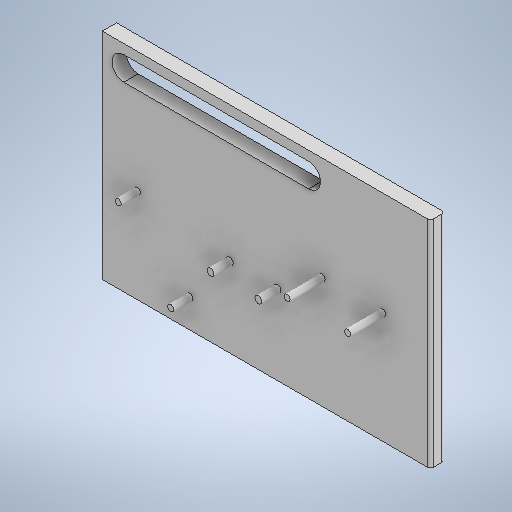
# Autodesk Inventor part: polka
Saved by Autodesk Inventor 2025.2 (Build 292293000, 293)
## iProperties
Created: 2026-10-25
Part Number: polka
Material: Generic
Document SubType Name: Modeling
Designer: Kacper
Density: 1 g/cm^3
Appearance: Default
Author: Kacper
Autodesk Inventor part; units mm, degrees
ref_plane "YZ Plane" through (0, 0, 0) normal (1, 0, 0) x (0, 1, 0)
ref_plane "XZ Plane" through (0, 0, 0) normal (0, 1, 0) x (-1, 0, 0)
ref_plane "XY Plane" through (0, 0, 0) normal (0, 0, 1) x (1, 0, 0)
sketch "Sketch1" plane through (0, 0, 0) normal (0, 0, 1) x (1, 0, 0)
  line L0 (-51.5, 33.75) -> (51.5, 33.75)
  line L1 (51.5, 33.75) -> (51.5, -33.75)
  line L2 (51.5, -33.75) -> (-51.5, -33.75)
  line L3 (-51.5, -33.75) -> (-51.5, 33.75)
  line L4 (-51.5, 33.75) -> (51.5, -33.75) construction
  line L5 (51.5, 33.75) -> (-51.5, -33.75) construction
  point P0 (0, 0)
  dimension "d1" = 67.5
  dimension "d2" = 103
  constraints: 12 end point, 2 midpoint, 2 parallel, 1 horizontal, 1 perpendicular
  measures "d1" distance of L0.end L1.end
  measures "d2" distance of L0.start L0.end
extrude "Extrusion1" add sketch "Sketch1" along normal blind 4.5
sketch "Sketch2" plane through (0, 0, 4.5) normal (0, 0, 1) x (1, 0, 0)
  line L0 (-51.5, -33.75) -> (51.5, -33.75) projected
  line L1 (51.5, -33.75) -> (51.5, 33.75) projected
  line L2 (51.5, 33.75) -> (-51.5, 33.75) projected
  line L3 (-51.5, 33.75) -> (-51.5, -33.75) projected
  line L4 (-44.75, 27) -> (13.25, 27) construction
  line L5 (-44.75, 23.25) -> (13.25, 23.25)
  line L6 (13.25, 30.75) -> (-44.75, 30.75)
  arc A0 (-44.75, 30.75) -> (-44.75, 23.25) centre (-44.75, 27) ccw
  arc A1 (13.25, 23.25) -> (13.25, 30.75) centre (13.25, 27) ccw
  point P0 (0, 0)
  point P1 (-15.75, 27)
  point P2 (17, 27)
  point P3 (-48.5, 27)
  point P4 (-15.75, 30.75)
  point P5 (-15.75, 23.25)
  dimension "d6" = 3
  dimension "d7" = 7.5
  dimension "d8" = 3
  dimension "d9" = 58
  constraints: 8 end point, 6 point on circle, 4 tangent, 3 midpoint, 2 centre point, 2 parallel, 1 horizontal
  measures "d6" distance from line of L3 point (-48.5, 27)
  measures "d7" distance of point (-15.75, 30.75) point (-15.75, 23.25)
  measures "d8" distance between parallel lines of L2 L6
  measures "d9" distance of L6.start L6.end
extrude "Extrusion2" cut sketch "Sketch2" against normal up to surface (4.5 mm away) contours A0 L6 A1 L5
sketch "Sketch3" plane through (0, 0, 4.5) normal (0, 0, 1) x (1, 0, 0)
  arc A0 (13.25, 23.25) -> (13.25, 30.75) centre (13.25, 27) ccw projected
  line L0 (13.25, 23.25) -> (-44.75, 23.25) projected
  arc A1 (-44.75, 30.75) -> (-44.75, 23.25) centre (-44.75, 27) ccw projected
  line L1 (-44.75, 30.75) -> (13.25, 30.75) projected
  line L2 (-51.5, -33.75) -> (51.5, -33.75) projected
  line L3 (51.5, -33.75) -> (51.5, 33.75) projected
  line L4 (51.5, 33.75) -> (-51.5, 33.75) projected
  line L5 (-51.5, 33.75) -> (-51.5, -33.75) projected
  circle A2 centre (17.5, 1.25) radius 0.975
  circle A3 centre (36.5, 1.25) radius 0.975
  point P0 (0, 0)
  dimension "d12" = 1.95
  dimension "d13" = 1.95
  dimension "d14" = 19
  dimension "d15" = 35
  dimension "d16" = 15
  dimension "d17" = 35
  constraints: 2 centre point
  measures "d12" diameter of A2
  measures "d13" diameter of A3
  measures "d14" distance of A3.centre A2.centre
  measures "d15" distance from line of L2 A3.centre
  measures "d16" distance from line of A3.centre L3
  measures "d17" distance from line of L2 A2.centre
extrude "Extrusion3" add sketch "Sketch3" along normal blind 11 contours A2 | A3
sketch "Sketch4" plane through (0, 0, 4.5) normal (0, 0, 1) x (1, 0, 0)
  circle A0 centre (36.5, 1.25) radius 0.975 projected
  circle A1 centre (17.5, 1.25) radius 0.975 projected
  arc A2 (13.25, 23.25) -> (13.25, 30.75) centre (13.25, 27) ccw projected
  line L0 (13.25, 23.25) -> (-44.75, 23.25) projected
  arc A3 (-44.75, 30.75) -> (-44.75, 23.25) centre (-44.75, 27) ccw projected
  line L1 (-44.75, 30.75) -> (13.25, 30.75) projected
  line L2 (-51.5, -33.75) -> (51.5, -33.75) projected
  line L3 (51.5, -33.75) -> (51.5, 33.75) projected
  line L4 (51.5, 33.75) -> (-51.5, 33.75) projected
  line L5 (-51.5, 33.75) -> (-51.5, -33.75) projected
  circle A4 centre (3.5, -8.75) radius 1.1
  circle A5 centre (-11.5, -8.75) radius 1.1
  circle A6 centre (-24, -24.75) radius 0.975
  circle A7 centre (-40.5, -4.25) radius 0.975
  point P0 (0, 0)
  dimension "d20" = 2.2
  dimension "d21" = 2.2
  dimension "d22" = 15
  dimension "d23" = 10
  dimension "d26" = 25
  dimension "d27" = 55
  dimension "d28" = 1.95
  dimension "d29" = 1.95
  dimension "d30" = 20.5
  dimension "d31" = 16.5
  dimension "d32" = 9
  dimension "d34" = 11
  constraints: 4 centre point
  measures "d20" diameter of A5
  measures "d21" diameter of A4
  measures "d22" distance of A4.centre A5.centre
  measures "d23" vertical distance of A1.centre A4.centre
  measures "d26" distance from line of L2 A5.centre
  measures "d27" distance from line of L5 A4.centre
  measures "d28" diameter of A7
  measures "d29" diameter of A6
  measures "d30" vertical distance of A7.centre A6.centre
  measures "d31" horizontal distance of A7.centre A6.centre
  measures "d32" distance from line of L2 A6.centre
  measures "d34" distance from line of L5 A7.centre
extrude "Extrusion4" add sketch "Sketch4" along normal blind 6 contours A4 | A5 | A6 | A7
fillet "Fillet1" radius 1 2 edges at (51.5, 0, 4.5) (51.5, 0, 0)
body "Solid1"
